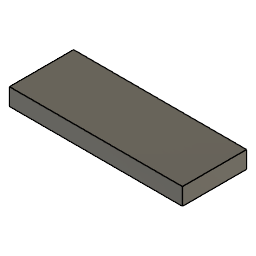
motor block (Autodesk Fusion 360 design; units mm, degrees)
part number: 2025-11-06-10-54-43-948
Autodesk Fusion 360 part; units mm, degrees
sketch "Sketch1" plane through (0, 0, 0) normal (0, 0, 1) x (1, 0, 0)
  line L0 (0, 0) -> (42.3, 0)
  line L1 (42.3, 0) -> (42.3, 15.7)
  line L2 (42.3, 15.7) -> (0, 15.7)
  line L3 (0, 15.7) -> (0, 0)
  dimension "d6" = 42.3
  dimension "d7" = 15.7
  constraint coincident L0.start L3.end
  constraint horizontal L0
  constraint perpendicular L0 L1
  constraint perpendicular L1 L2
  constraint perpendicular L0 L3
  measures "d6" distance of L0.start L0.end
  measures "d7" distance of L0.end L1.end
extrude "Extrude2" add sketch "Sketch1" along normal blind 4.2
